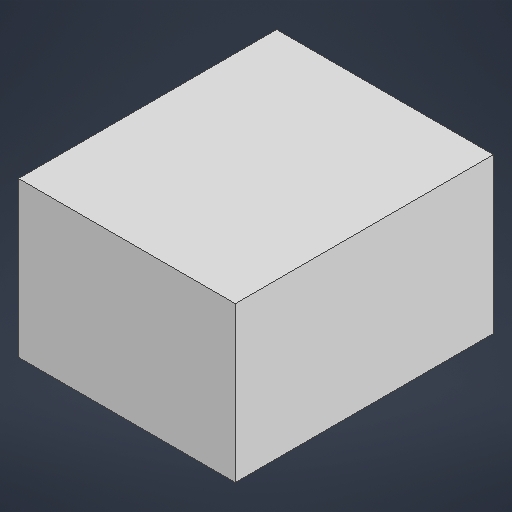
# Autodesk Inventor part: DUMMY-KCD1
Saved by Autodesk Inventor 2027.1 (Build 311270010, 270A)
## iProperties
Created: 2026-10-28
Part Number: DUMMY-KCD1
Material: Generic
Description: KCD1 rocker switch body
Document SubType Name: Modeling
Designer: shyan
Density: 1 g/cm^3
Appearance: Default
Mass: 8 g
Author: shyan
Autodesk Inventor part; units mm, degrees
ref_plane "YZ Plane" through (0, 0, 0) normal (1, 0, 0) x (0, 1, 0)
ref_plane "XZ Plane" through (0, 0, 0) normal (0, 1, 0) x (-1, 0, 0)
ref_plane "XY Plane" through (0, 0, 0) normal (0, 0, 1) x (1, 0, 0)
sketch "sk_body" plane through (0, 0, 0) normal (0, 0, 1) x (1, 0, 0)
  line L0 (-10.5, -7.5) -> (10.5, -7.5)
  line L1 (10.5, -7.5) -> (10.5, 7.5)
  line L2 (10.5, 7.5) -> (-10.5, 7.5)
  line L3 (-10.5, 7.5) -> (-10.5, -7.5)
  line L4 (-14.7, 0) -> (14.7, 0) construction
  line L5 (0, -10.5) -> (0, 10.5) construction
  point P0 (0, 0)
  dimension "d0" = 21
  dimension "d1" = 15
  constraints: 8 end point, 2 parallel, 1 horizontal, 1 perpendicular, 2 other
  measures "d0" distance of L0.start L0.end
  measures "d1" distance of L0.end L1.end
extrude "Body" add sketch "sk_body" along normal blind 25
equation "\"d0\" = sw_W"
equation "\"d1\" = sw_D"
equation "\"d2\" = sw_H"
equation "\"sw_W\" = 21"
equation "\"sw_D\" = 15"
equation "\"sw_H\" = 25"
body "Solid1"
